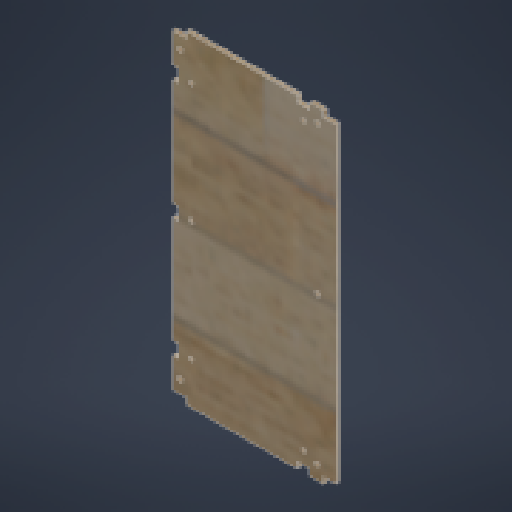
# Autodesk Inventor part: Stage
Saved by Autodesk Inventor 2027.1 (Build 311270010, 270A)
## iProperties
Created: 2026-10-10
Part Number: Stage
Material: 木材 (カエデ材)
Document SubType Name: Modeling
Designer: Takuya Kamada
Density: 0.67 g/cm^3
Appearance: ナチュラル カエデ材 - 光沢 濃い着色
Author: Takuya Kamada
Autodesk Inventor part; units mm, degrees
ref_plane "YZ Plane" through (0, 0, 0) normal (1, 0, 0) x (0, 1, 0)
ref_plane "XZ Plane" through (0, 0, 0) normal (0, 1, 0) x (-1, 0, 0)
ref_plane "XY Plane" through (0, 0, 0) normal (0, 0, 1) x (1, 0, 0)
sketch "スケッチ1" plane through (0, 0, 0) normal (0, 0, 1) x (1, 0, 0)
  circle A0 centre (-8.6886, -94.0668) radius 1.5
  circle A1 centre (-8.25, 0) radius 1.5
  circle A2 centre (-8.25, 94) radius 1.5
  line L0 (3.25, -99) -> (-13.25, -99)
  line L1 (3.25, 99) -> (3.25, -99)
  line L2 (3.25, 99) -> (-13.25, 99)
  line L3 (-13.25, 89) -> (-13.25, 99)
  line L4 (-6.25, 89) -> (-13.25, 89)
  line L5 (-3.25, 86) -> (-6.25, 89)
  line L6 (-3.25, 8) -> (-3.25, 86)
  line L7 (-6.25, 5) -> (-3.25, 8)
  line L8 (-6.25, 5) -> (-13.25, 5)
  line L9 (-13.25, -5) -> (-13.25, 5)
  line L10 (-6.25, -5) -> (-13.25, -5)
  line L11 (-3.25, -8) -> (-6.25, -5)
  line L12 (-3.25, -86) -> (-3.25, -8)
  line L13 (-6.25, -89) -> (-3.25, -86)
  line L14 (-6.25, -89) -> (-13.25, -89)
  line L15 (-13.25, -99) -> (-13.25, -89)
  line L16 (3.25, -99) -> (-96.75, -99)
  line L17 (-96.75, -99) -> (-96.75, 99)
  line L18 (-96.75, 99) -> (3.25, 99)
  line L19 (3.25, 99) -> (3.25, -99)
  point P0 (0, 0)
  dimension "d0" = 100
  constraints: 40 end point, 3 centre point, 1 point on line
  measures "d0" distance of L17.end L18.end
extrude "押し出し1" add sketch "スケッチ1" along normal blind 2.5
sketch "スケッチ2" plane through (0, 0, 2.5) normal (0, 0, 1) x (1, 0, 0)
  line L0 (3.25, -99) -> (3.25, 99) projected
  line L1 (3.25, 99) -> (-96.75, 99) projected
  line L2 (-96.75, 99) -> (-96.75, -99) projected
  line L3 (-96.75, -99) -> (3.25, -99) projected
  circle A0 centre (-8.6886, -94.0668) radius 1.5 projected
  circle A1 centre (-8.25, 0) radius 1.5 projected
  circle A2 centre (-8.25, 94) radius 1.5 projected
  line L4 (-100.75, -102.9439) -> (-100.75, 102.9439) projected
  line L5 (-101.7161, -91) -> (-96.75, -91) projected
  line L6 (-101.7161, -91) -> (-101.7161, -99) projected
  line L7 (-96.75, -99) -> (-101.7161, -99) projected
  line L8 (-96.75, -91) -> (-96.75, -99) projected
  line L9 (-101.7161, 99) -> (-96.75, 99) projected
  line L10 (-101.7161, 99) -> (-101.7161, 91) projected
  line L11 (-96.75, 91) -> (-101.7161, 91) projected
  line L12 (-96.75, 99) -> (-96.75, 91) projected
  point P0 (0, 0)
  point P1 (-100.75, 91)
  point P2 (-100.75, -91)
extrude "押し出し2" add sketch "スケッチ2" against normal blind 2.5 contours L5 L4 L11 L2
sketch "スケッチ3" plane through (0, 0, 2.5) normal (0, 0, 1) x (1, 0, 0)
  line L0 (3.25, -99) -> (3.25, 99) projected
  line L1 (3.25, 99) -> (-96.75, 99) projected
  line L2 (-96.75, 99) -> (-96.75, 91) projected
  line L3 (-96.75, 91) -> (-100.75, 91) projected
  line L4 (-100.75, 91) -> (-100.75, -91) projected
  line L5 (-100.75, -91) -> (-96.75, -91) projected
  line L6 (-96.75, -91) -> (-96.75, -99) projected
  line L7 (-96.75, -99) -> (3.25, -99) projected
  circle A0 centre (-8.6886, -94.0668) radius 1.5 projected
  circle A1 centre (-8.25, 0) radius 1.5 projected
  circle A2 centre (-8.25, 94) radius 1.5 projected
  line L8 (-13.25, 103.9661) -> (-13.25, 99) projected
  line L9 (-13.25, 103.9661) -> (-21.25, 103.9661) projected
  line L10 (-21.25, 99) -> (-21.25, 103.9661) projected
  line L11 (-13.25, 99) -> (-21.25, 99) projected
  line L12 (-4.5064, 103) -> (-4.5064, 103.9012) projected
  line L13 (-99.8415, 103) -> (-4.5064, 103) projected
  line L14 (-4.5064, 103) -> (-4.5064, 99)
  line L15 (-84.75, 103.9661) -> (-84.75, 99) projected
  line L16 (-84.75, 103.9661) -> (-92.75, 103.9661) projected
  line L17 (-92.75, 99) -> (-92.75, 103.9661) projected
  line L18 (-84.75, 99) -> (-92.75, 99) projected
  point P0 (0, 0)
  point P1 (-84.75, 103)
  point P2 (-21.25, 103)
  point P3 (-13.25, 103)
  constraints: 2 end point, 1 perpendicular, 1 point on line
extrude "押し出し3" add sketch "スケッチ3" against normal blind 2.5 contours L1 L8 L13 L14 | L1 L15 L13 L10
sketch "スケッチ4" plane through (0, 0, 2.5) normal (0, 0, 1) x (1, 0, 0)
  line L0 (3.25, -99) -> (3.25, 99) projected
  line L1 (3.25, 99) -> (-4.5064, 99) projected
  line L2 (-4.5064, 99) -> (-4.5064, 103) projected
  line L3 (-4.5064, 103) -> (-13.25, 103) projected
  line L4 (-13.25, 103) -> (-13.25, 99) projected
  line L5 (-13.25, 99) -> (-21.25, 99) projected
  line L6 (-21.25, 99) -> (-21.25, 103) projected
  line L7 (-21.25, 103) -> (-84.75, 103) projected
  line L8 (-84.75, 103) -> (-84.75, 99) projected
  line L9 (-84.75, 99) -> (-96.75, 99) projected
  line L10 (-96.75, 99) -> (-96.75, 91) projected
  line L11 (-96.75, 91) -> (-100.75, 91) projected
  line L12 (-100.75, 91) -> (-100.75, -91) projected
  line L13 (-100.75, -91) -> (-96.75, -91) projected
  line L14 (-96.75, -91) -> (-96.75, -99) projected
  line L15 (-96.75, -99) -> (3.25, -99) projected
  circle A0 centre (-8.6886, -94.0668) radius 1.5 projected
  circle A1 centre (-8.25, 0) radius 1.5 projected
  circle A2 centre (-8.25, 94) radius 1.5 projected
  line L16 (-192.9955, -197.0552) -> (-99.8415, -103.9012) projected
  line L17 (-21.25, -197.0552) -> (-192.9955, -197.0552) projected
  line L18 (-21.25, -184.1171) -> (-21.25, -197.0552) projected
  line L19 (-13.25, -184.1171) -> (-21.25, -184.1171) projected
  line L20 (-13.25, -197.0552) -> (-13.25, -184.1171) projected
  line L21 (13.6022, -197.0552) -> (-13.25, -197.0552) projected
  ellipse E0 centre (61.236, -170.0854) end of major axis (20.6499, -64.1768) minor radius 54.2705 (8.5688, -184.1171) -> (13.6022, -197.0552) ccw projected
  spline S0 degree 4 poles (-4.5064, -103.9012) (-4.5064, -127.7314) (-2.5129, -145.2049) (1.3825, -163.9104) (8.5688, -184.1171) knots 1 1 1 1 1 1.868208 1.868208 1.868208 1.868208 1.868208 projected
  line L22 (-99.8415, -103.9012) -> (-4.5064, -103.9012) projected
  line L23 (-4.5064, 103) -> (-84.75, 103)
  line L24 (-84.75, 103) -> (-84.75, 99)
  line L25 (-84.75, 99) -> (-4.5064, 99)
  line L26 (-4.5064, 99) -> (-4.5064, 103)
  line L27 (3.25, 0) -> (-100.75, 0)
  line L28 (-4.5064, -103) -> (-13.25, -103)
  line L29 (-13.25, -103) -> (-13.25, -99)
  line L30 (-21.25, -103) -> (-84.75, -103)
  line L31 (-4.5064, -103) -> (-84.75, -103)
  line L32 (-84.75, -99) -> (-4.5064, -99)
  line L33 (-4.5064, -99) -> (-4.5064, -103)
  line L34 (-84.75, -103) -> (-84.75, -99)
  line L35 (-21.25, 103) -> (-21.25, -103)
  point P0 (0, 0)
  point P1 (-4.5064, -99)
  point P2 (-21.25, -99)
  constraints: 26 end point, 8 symmetric about line, 3 parallel, 2 midpoint, 1 horizontal, 1 perpendicular, 1 vertical, 1 other
extrude "押し出し4" add sketch "スケッチ4" against normal blind 2.5 contours L33 L28 L29 L15 | L35 L30 L34 L15
sketch "スケッチ5" plane through (0, 0, 2.5) normal (0, 0, 1) x (1, 0, 0)
  line L0 (-96.75, 4) -> (-96.75, -4) projected
  line L1 (-96.75, -4) -> (-101.7161, -4) projected
  line L2 (-101.7161, 4) -> (-96.75, 4) projected
  line L3 (-100.75, 91) -> (-100.75, -91) projected
  point P0 (0, 0)
  point P1 (-100.75, 4)
  point P2 (-100.75, -4)
extrude "押し出し5" cut sketch "スケッチ5" against normal blind 2.5
sketch "スケッチ6" plane through (0, 0, 2.5) normal (0, 0, 1) x (1, 0, 0)
  line L0 (-91.8415, -99) -> (-91.8415, -103.9661) projected
  line L1 (-99.8415, -103) -> (-4.5064, -103) projected
  line L2 (-84.75, -99) -> (-84.75, -103) projected
  line L3 (-96.75, -99) -> (-84.75, -99) projected
  line L4 (-96.75, -91) -> (-96.75, -99) projected
  line L5 (-100.75, -91) -> (-96.75, -91) projected
  line L6 (-100.75, -102.9439) -> (-100.75, 102.9439) projected
  line L7 (-99.8415, -103) -> (-100.75, -102.9439)
  line L8 (-96.75, -4) -> (-100.75, -4) projected
  line L9 (-100.75, -4) -> (-100.75, -91) projected
  line L10 (-100.75, -91) -> (-96.75, -91) projected
  line L11 (-96.75, -91) -> (-96.75, -99) projected
  line L12 (-96.75, -99) -> (-84.75, -99) projected
  line L13 (-84.75, -99) -> (-84.75, -103) projected
  line L14 (-84.75, -103) -> (-21.25, -103) projected
  line L15 (-21.25, -103) -> (-21.25, -99) projected
  line L16 (-21.25, -99) -> (-13.25, -99) projected
  line L17 (-13.25, -99) -> (-13.25, -103) projected
  line L18 (-13.25, -103) -> (-4.5064, -103) projected
  line L19 (-4.5064, -103) -> (-4.5064, -99) projected
  line L20 (-4.5064, -99) -> (3.25, -99) projected
  line L21 (3.25, -99) -> (3.25, 99) projected
  line L22 (3.25, 99) -> (-4.5064, 99) projected
  line L23 (-4.5064, 99) -> (-4.5064, 103) projected
  line L24 (-4.5064, 103) -> (-13.25, 103) projected
  line L25 (-13.25, 103) -> (-13.25, 99) projected
  line L26 (-13.25, 99) -> (-21.25, 99) projected
  line L27 (-21.25, 99) -> (-21.25, 103) projected
  line L28 (-21.25, 103) -> (-84.75, 103) projected
  line L29 (-84.75, 103) -> (-84.75, 99) projected
  line L30 (-84.75, 99) -> (-96.75, 99) projected
  line L31 (-96.75, 99) -> (-96.75, 91) projected
  line L32 (-96.75, 91) -> (-100.75, 91) projected
  line L33 (-100.75, 91) -> (-100.75, 4) projected
  line L34 (-100.75, 4) -> (-96.75, 4) projected
  line L35 (-96.75, 4) -> (-96.75, -4) projected
  circle A0 centre (-8.6886, -94.0668) radius 1.5 projected
  circle A1 centre (-8.25, 0) radius 1.5 projected
  circle A2 centre (-8.25, 94) radius 1.5 projected
  line L36 (-84.75, 103) -> (-100.75, 102.9439)
  point P0 (0, 0)
  constraints: 4 end point
extrude "押し出し6" add sketch "スケッチ6" against normal blind 2.5 contours L3 L2 L1 L0 | L0 L1 L7 L6 L5 L4 L3 | L6 L36 L29 L30 L31 L32
sketch "スケッチ7" plane through (0, 0, 2.5) normal (0, 0, 1) x (1, 0, 0)
  line L0 (-99.8415, -103.9661) -> (-99.8415, -99) projected
  line L1 (-99.8415, -103.9661) -> (-91.8415, -103.9661) projected
  line L2 (-91.8415, -99) -> (-91.8415, -103.9661) projected
  line L3 (-99.8415, -99) -> (-91.8415, -99) projected
  line L4 (-91.8415, 103.9661) -> (-91.8415, 99) projected
  line L5 (-91.8415, 103.9661) -> (-99.8415, 103.9661) projected
  line L6 (-99.8415, 99) -> (-99.8415, 103.9661) projected
  line L7 (-91.8415, 99) -> (-99.8415, 99) projected
  line L8 (-96.75, -4) -> (-100.75, -4) projected
  line L9 (-100.75, -4) -> (-100.75, -102.9439) projected
  line L10 (-100.75, -102.9439) -> (-99.8415, -103) projected
  line L11 (-99.8415, -103) -> (-21.25, -103) projected
  line L12 (-21.25, -103) -> (-21.25, -99) projected
  line L13 (-21.25, -99) -> (-13.25, -99) projected
  line L14 (-13.25, -99) -> (-13.25, -103) projected
  line L15 (-13.25, -103) -> (-4.5064, -103) projected
  line L16 (-4.5064, -103) -> (-4.5064, -99) projected
  line L17 (-4.5064, -99) -> (3.25, -99) projected
  line L18 (3.25, -99) -> (3.25, 99) projected
  line L19 (3.25, 99) -> (-4.5064, 99) projected
  line L20 (-4.5064, 99) -> (-4.5064, 103) projected
  line L21 (-4.5064, 103) -> (-13.25, 103) projected
  line L22 (-13.25, 103) -> (-13.25, 99) projected
  line L23 (-13.25, 99) -> (-21.25, 99) projected
  line L24 (-21.25, 99) -> (-21.25, 103) projected
  line L25 (-21.25, 103) -> (-84.75, 103) projected
  line L26 (-84.75, 103) -> (-100.75, 102.9439) projected
  line L27 (-100.75, 102.9439) -> (-100.75, 4) projected
  line L28 (-100.75, 4) -> (-96.75, 4) projected
  line L29 (-96.75, 4) -> (-96.75, -4) projected
  circle A0 centre (-8.6886, -94.0668) radius 1.5 projected
  circle A1 centre (-8.25, 0) radius 1.5 projected
  circle A2 centre (-8.25, 94) radius 1.5 projected
  line L30 (-91.8415, 102.9752) -> (-100.75, 102.9752)
  line L31 (-100.75, 102.9752) -> (-100.75, 99)
  line L32 (-100.75, 99) -> (-91.8415, 99)
  line L33 (-91.8415, 99) -> (-91.8415, 102.9752)
  line L34 (-91.8415, -99) -> (-100.75, -99)
  line L35 (-100.75, -99) -> (-100.75, -102.9439)
  line L36 (-100.75, -102.9439) -> (-91.8415, -102.9439)
  line L37 (-91.8415, -102.9439) -> (-91.8415, -99)
  point P0 (0, 0)
  point P1 (-91.8415, -103)
  constraints: 16 end point, 4 parallel, 4 point on line, 2 horizontal, 2 perpendicular
extrude "押し出し7" cut sketch "スケッチ7" against normal blind 2.5 contours L10 L36 L0 | L0 L36 L2 L11 | L36 L9 L34 L0 | L0 L3 L2 L36 | L27 L26 L6 L32 | L6 L26 L4 L7
sketch "スケッチ8" plane through (0, 0, 2.5) normal (0, 0, 1) x (1, 0, 0)
  line L0 (-101.7161, 80) -> (-96.75, 80) projected
  line L1 (-96.75, 80) -> (-96.75, 72) projected
  line L2 (-96.75, 72) -> (-101.7161, 72) projected
  line L3 (-100.75, 99) -> (-100.75, 4) projected
  line L4 (-101.7161, -72) -> (-96.75, -72) projected
  line L5 (-96.75, -72) -> (-96.75, -80) projected
  line L6 (-96.75, -80) -> (-101.7161, -80) projected
  line L7 (-100.75, -4) -> (-100.75, -99) projected
  point P0 (0, 0)
  point P1 (-100.75, -72)
  point P2 (-100.75, -80)
  point P3 (-100.75, 80)
  point P4 (-100.75, 72)
extrude "押し出し8" cut sketch "スケッチ8" against normal blind 2.5
sketch "スケッチ9" plane through (0, 0, 2.5) normal (0, 0, 1) x (1, 0, 0)
  circle A0 centre (-95.8415, 91) radius 1.5
  circle A1 centre (-88.75, 76) radius 1.5
  circle A2 centre (-88.75, 0) radius 1.5
  circle A3 centre (-88.75, -76) radius 1.5
  circle A4 centre (-95.8415, -91) radius 1.5
  circle A5 centre (-17.25, -91) radius 1.5
  circle A6 centre (-17.25, 91) radius 1.5
  point P0 (0, 0)
extrude "押し出し9" cut sketch "スケッチ9" against normal blind 2.5
